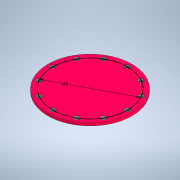
# Autodesk Inventor part: fund felinar_gaurit
Saved by Autodesk Inventor 2022.6 (Build 266554000, 554)
## iProperties
Created: 2025-06-10
Part Number: fund felinar_gaurit
Material: Generic
Document SubType Name: Modeling
Designer: Dragos Macovei
Density: 1 g/cm^3
Appearance: Default
Author: Dragos Macovei
Autodesk Inventor part; units mm, degrees
ref_plane "YZ Plane" through (0, 0, 0) normal (1, 0, 0) x (0, 1, 0)
ref_plane "XZ Plane" through (0, 0, 0) normal (0, 1, 0) x (-1, 0, 0)
ref_plane "XY Plane" through (0, 0, 0) normal (0, 0, 1) x (1, 0, 0)
sketch "Sketch1" plane through (0, 0, 0) normal (0, 1, 0) x (-1, 0, 0)
  circle A0 centre (0, 0) radius 90
  dimension "d0" = 180
  constraints: 1 centre point, 1 coincident
  measures "d0" diameter of A0
extrude "Extrusion1" add sketch "Sketch1" along normal blind 6
sketch "Sketch2" plane through (0, 6, 0) normal (0, 1, 0) x (1, 0, 0)
  circle A0 centre (0, 0) radius 80
  dimension "d3" = 160
  constraints: 1 centre point, 1 coincident
  measures "d3" diameter of A0
sketch "Sketch3" plane through (0, 6, 0) normal (0, 1, 0) x (1, 0, 0)
  circle A0 centre (0, 0) radius 90 projected
  line L0 (0, 99.4202) -> (0, -108.8081) construction
  line L1 (-137.3379, 0) -> (196.8442, 0) construction
  circle A1 centre (0, 0) radius 80 projected
  circle A2 centre (0, 80) radius 5.25
  circle A3 centre (-40, 69.282) radius 5.25
  circle A4 centre (-69.282, 40) radius 5.25
  circle A5 centre (-80, 0) radius 5.25
  circle A6 centre (-69.282, -40) radius 5.25
  circle A7 centre (-40, -69.282) radius 5.25
  circle A8 centre (0, -80) radius 5.25
  circle A9 centre (40, -69.282) radius 5.25
  circle A10 centre (69.282, -40) radius 5.25
  circle A11 centre (80, 0) radius 5.25
  circle A12 centre (69.282, 40) radius 5.25
  circle A13 centre (40, 69.282) radius 5.25
  dimension "d25" = 10.5
  dimension "d28" = 360
  constraints: 12 centre point, 4 end point, 1 horizontal, 1 point on line, 1 vertical, 1 vertical alignment, 26 other
  measures "d25" diameter of A2
extrude "Extrusion2" cut sketch "Sketch3" against normal through all contours A1 A11 | A1 A11 | A12 A1 | A1 A12 | A10 A1 | A1 A10 | A13 A1 | A1 A13 | A9 A1 | A1 A9 | A2 A1 | A1 A2 | A8 A1 | A1 A8 | A3 A1 | A1 A3 | A7 A1 | A1 A7 | A4 A1 | A1 A4 | A6 A1 | A1 A6 | A5 A1 | A1 A5
body "Solid1"
